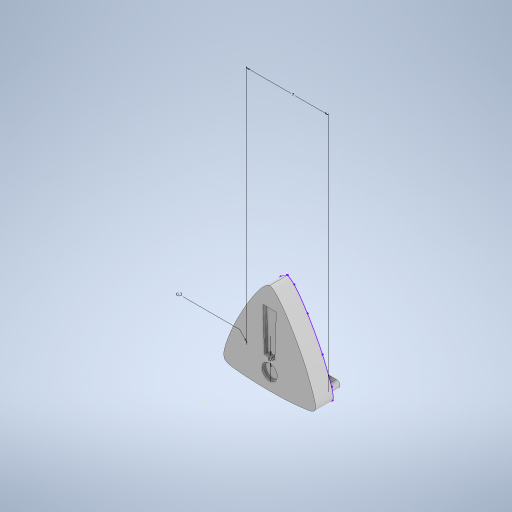
# Autodesk Inventor part: Señal
Saved by Autodesk Inventor 2024.2 (Build 282272000, 272)
## iProperties
Created: 2025-09-19
Part Number: Señal
Material: Genérico
Document SubType Name: Modeling
Designer: Pablo
Density: 1 g/cm^3
Appearance: Valor por defecto
Author: Pablo
Autodesk Inventor part; units mm, degrees
ref_plane "YZ Plane" through (0, 0, 0) normal (1, 0, 0) x (0, 1, 0)
ref_plane "XZ Plane" through (0, 0, 0) normal (0, 1, 0) x (-1, 0, 0)
ref_plane "XY Plane" through (0, 0, 0) normal (0, 0, 1) x (1, 0, 0)
sketch "Boceto1" plane through (0, 0, 0) normal (0, 0, 1) x (1, 0, 0)
  spline S0 degree 4 poles (7.1961, 13.0337) (6.7277, 12.9463) (5.82, 11.7176) (4.4759, 9.4808) (3.5217, 7.1557) (3.043, 5.5512) (3.8795, 5.4222) (5.5843, 5.2402) (8.8311, 5.2059) (10.3184, 5.4702) (11.4215, 5.5047) (10.8175, 7.1372) (9.9665, 9.4655) (8.5557, 11.7261) (7.6895, 12.9461) (7.1961, 13.0337) knots 0 0 0 0 0 0.166206 0.240382 0.304772 0.363687 0.429349 0.498505 0.568443 0.63464 0.6941 0.759218 0.83333 1 1 1 1 1
  line L0 (6.6288, 11.3576) -> (7.7633, 11.3576)
  line L1 (6.7535, 7.7468) -> (6.6288, 11.3576)
  line L2 (7.7633, 11.3576) -> (7.6386, 7.7468)
  line L3 (7.6386, 7.7468) -> (6.7535, 7.7468)
  circle A0 centre (7.1961, 6.6468) radius 0.65
  line L4 (7.1961, 6.4468) -> (3.9961, 6.4468)
  arc A1 (3.9961, 6.4468) -> (3.6961, 6.1468) centre (3.9961, 6.1468) ccw
  arc A2 (3.6961, 6.1468) -> (3.9961, 5.8468) centre (3.9961, 6.1468) ccw
  line L5 (3.9961, 5.8468) -> (7.1961, 5.8468)
  line L6 (10.3961, 5.8468) -> (7.1961, 5.8468)
  line L7 (7.1961, 6.4468) -> (10.3961, 6.4468)
  arc A3 (10.6961, 6.1468) -> (10.3961, 6.4468) centre (10.3961, 6.1468) ccw
  arc A4 (10.3961, 5.8468) -> (10.6961, 6.1468) centre (10.3961, 6.1468) ccw
  point P0 (0, 0)
  point P1 (7.1961, 10.9469)
  point P2 (5.4871, 11.0718)
  point P3 (4.1948, 8.6932)
  point P4 (3.4082, 6.6807)
  point P5 (3.3316, 5.7459)
  point P6 (3.6961, 5.4852)
  point P7 (5.2261, 5.3074)
  point P8 (9.0991, 5.3074)
  point P9 (10.5926, 5.4852)
  point P10 (11.056, 5.7401)
  point P11 (10.9758, 6.6676)
  point P12 (10.1954, 8.6849)
  point P13 (8.9167, 11.0663)
  point P14 (7.7842, 12.6356)
  point P15 (3.6961, 6.1468)
  dimension "d0" = 0.3
  dimension "d1" = 0.6
  dimension "d2" = 7
  constraints: 16 end point, 8 point on circle, 5 centre point, 2 horizontal, 2 tangent, 1 concentric, 15 other
  measures "d0" radius of A1
  measures "d1" distance between parallel lines of L5 L4
  measures "d2" distance of A1.end A3.start
extrude "Extrusión1" add sketch "Boceto1" along normal blind 1.5 contours S0 | A0 L7 A3 A4 L6 L5 A2 A1 L4
extrude "Extrusión2" add sketch "Boceto1" against normal blind 1 contours L4 L7 A0 | A0 L7 A3 A4 L6 L5 A2 A1 L4 picked at (6.8043, 6.4018)
extrude "Extrusión3" add sketch "Boceto1" along normal blind 1.2 contours L0 L2 L3 L1 | A0 L7 L4 | L4 L7 A0
